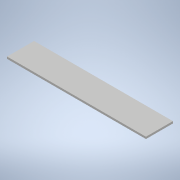
# Autodesk Inventor part: blat
Saved by Autodesk Inventor 2022.6 (Build 266554000, 554)
## iProperties
Created: 2026-10-28
Part Number: blat
Material: Generic
Document SubType Name: Modeling
Designer: Dragos Macovei
Density: 1 g/cm^3
Appearance: Default
Author: Dragos Macovei
Autodesk Inventor part; units mm, degrees
ref_plane "YZ Plane" through (0, 0, 0) normal (1, 0, 0) x (0, 1, 0)
ref_plane "XZ Plane" through (0, 0, 0) normal (0, 1, 0) x (-1, 0, 0)
ref_plane "XY Plane" through (0, 0, 0) normal (0, 0, 1) x (1, 0, 0)
sketch "Sketch1" plane through (0, 0, 0) normal (0, 1, 0) x (-1, 0, 0)
  line L0 (-2486.8282, 174.7414) -> (8.1718, 174.7414)
  line L1 (8.1718, 174.7414) -> (8.1718, 659.7414)
  line L2 (8.1718, 659.7414) -> (-2486.8282, 659.7414)
  line L3 (-2486.8282, 659.7414) -> (-2486.8282, 174.7414)
  point P0 (0, 0)
  dimension "d0" = 485
  dimension "d1" = 2495
  constraints: 8 end point, 2 parallel, 1 horizontal, 1 perpendicular
  measures "d0" distance of L1.end L0.end
  measures "d1" distance of L1.end L2.end
extrude "Extrusion1" add sketch "Sketch1" along normal blind 36
body "Solid1"
